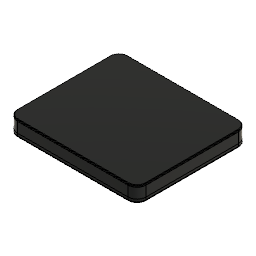
SafeWall-A-concept-v01 (Autodesk Fusion 360 design; units mm, degrees)
part number: 2026-10-03-23-20-51-672
part number: 2026-10-03-23-20-51-673
part number: 2026-10-03-23-20-51-674
part number: 2026-10-03-23-20-51-675
part number: 2026-10-03-23-20-51-676
Autodesk Fusion 360 part; units mm, degrees
sketch "01 Contact pad - silicone proposal_outline" plane through (0, 0, 0) normal (0, 0, 1) x (1, 0, 0) in component "01 Contact pad - silicone proposal"
  line L0 (9, 0) -> (119, 0)
  line L1 (128, 9) -> (128, 101)
  line L2 (119, 110) -> (9, 110)
  line L3 (0, 101) -> (0, 9)
  arc A0 (119, 0) -> (128, 9) centre (119, 9) ccw
  arc A1 (128, 101) -> (119, 110) centre (119, 101) ccw
  arc A2 (9, 110) -> (0, 101) centre (9, 101) ccw
  arc A3 (0, 9) -> (9, 0) centre (9, 9) ccw
extrude "01 Contact pad - silicone proposal" add sketch "01 Contact pad - silicone proposal_outline" along normal blind 0.6 makes body 1 in component "01 Contact pad - silicone proposal"
sketch "02 Rear panel - magnet pockets_outline" plane through (0, 0, 0) normal (0, 0, 1) x (1, 0, 0) in component "02 Rear panel - magnet pockets"
  line L0 (9, 0) -> (119, 0)
  line L1 (128, 9) -> (128, 101)
  line L2 (119, 110) -> (9, 110)
  line L3 (0, 101) -> (0, 9)
  arc A0 (119, 0) -> (128, 9) centre (119, 9) ccw
  arc A1 (128, 101) -> (119, 110) centre (119, 101) ccw
  arc A2 (9, 110) -> (0, 101) centre (9, 101) ccw
  arc A3 (0, 9) -> (9, 0) centre (9, 9) ccw
extrude "02 Rear panel - magnet pockets" add sketch "02 Rear panel - magnet pockets_outline" along normal blind 2.4 separate body makes body 2 in component "02 Rear panel - magnet pockets"
ref_plane "WorkPlane1" through (0, 0, 2.4) normal (0, 0, 1) x (1, 0, 0) in component "02 Rear panel - magnet pockets"
sketch "Magnet_ring_pocket" plane through (0, 0, 2.4) normal (0, 0, 1) x (1, 0, 0) in component "02 Rear panel - magnet pockets"
  circle A0 centre (64, 80) radius 27.55
  circle A1 centre (64, 80) radius 22.5
extrude "Ring pocket - depth provisional" cut sketch "Magnet_ring_pocket" against normal blind 2 bodies 2 in component "02 Rear panel - magnet pockets"
ref_plane "WorkPlane2" through (0, 0, 2.4) normal (0, 0, 1) x (1, 0, 0) in component "02 Rear panel - magnet pockets"
sketch "Orientation_pocket" plane through (0, 0, 2.4) normal (0, 0, 1) x (1, 0, 0) in component "02 Rear panel - magnet pockets"
  line L0 (61, 29.01) -> (67, 29.01)
  line L1 (67.5, 29.51) -> (67.5, 48.82)
  line L2 (67, 49.32) -> (61, 49.32)
  line L3 (60.5, 48.82) -> (60.5, 29.51)
  arc A0 (67, 29.01) -> (67.5, 29.51) centre (67, 29.51) ccw
  arc A1 (67.5, 48.82) -> (67, 49.32) centre (67, 48.82) ccw
  arc A2 (61, 49.32) -> (60.5, 48.82) centre (61, 48.82) ccw
  arc A3 (60.5, 29.51) -> (61, 29.01) centre (61, 29.51) ccw
extrude "Orientation pocket - depth provisional" cut sketch "Orientation_pocket" against normal blind 2 bodies 2 in component "02 Rear panel - magnet pockets"
sketch "03 Magnet ring SPACE ONLY - not magnet specification_outline" plane through (0, 0, 0) normal (0, 0, 1) x (1, 0, 0) in component "03 Magnet ring SPACE ONLY - not magnet specification"
  circle A0 centre (0, 0) radius 27.05
  circle A1 centre (0, 0) radius 23
extrude "03 Magnet ring SPACE ONLY - not magnet specification" add sketch "03 Magnet ring SPACE ONLY - not magnet specification_outline" along normal blind 1.2 separate body makes body 3 in component "03 Magnet ring SPACE ONLY - not magnet specification"
sketch "04 Orientation magnet SPACE ONLY_outline" plane through (0, 0, 0) normal (0, 0, 1) x (1, 0, 0) in component "04 Orientation magnet SPACE ONLY"
  line L0 (0, 0) -> (6, 0)
  line L1 (6, 0) -> (6, 19.31)
  line L2 (6, 19.31) -> (0, 19.31)
  line L3 (0, 19.31) -> (0, 0)
extrude "04 Orientation magnet SPACE ONLY" add sketch "04 Orientation magnet SPACE ONLY_outline" along normal blind 1.2 separate body makes body 4 in component "04 Orientation magnet SPACE ONLY"
sketch "Wall_ring" plane through (0, 0, 0) normal (0, 0, 1) x (1, 0, 0) in component "05 Perimeter walls - ports and fasteners unresolved"
  line L0 (9, 0) -> (119, 0)
  line L1 (128, 9) -> (128, 101)
  line L2 (119, 110) -> (9, 110)
  line L3 (0, 101) -> (0, 9)
  arc A0 (119, 0) -> (128, 9) centre (119, 9) ccw
  arc A1 (128, 101) -> (119, 110) centre (119, 101) ccw
  arc A2 (9, 110) -> (0, 101) centre (9, 101) ccw
  arc A3 (0, 9) -> (9, 0) centre (9, 9) ccw
  line L4 (9, 1.6) -> (119, 1.6)
  line L5 (126.4, 9) -> (126.4, 101)
  line L6 (119, 108.4) -> (9, 108.4)
  line L7 (1.6, 101) -> (1.6, 9)
  arc A4 (119, 1.6) -> (126.4, 9) centre (119, 9) ccw
  arc A5 (126.4, 101) -> (119, 108.4) centre (119, 101) ccw
  arc A6 (9, 108.4) -> (1.6, 101) centre (9, 101) ccw
  arc A7 (1.6, 9) -> (9, 1.6) centre (9, 9) ccw
extrude "Shell perimeter" add sketch "Wall_ring" along normal blind 10.2 separate body makes body 5 in component "05 Perimeter walls - ports and fasteners unresolved"
sketch "06 Battery reference - EEMB 3400mAh - not selected_outline" plane through (0, 0, 0) normal (0, 0, 1) x (1, 0, 0) in component "06 Battery reference - EEMB 3400mAh - not selected"
  line L0 (1.2, 0) -> (54.3, 0)
  line L1 (55.5, 1.2) -> (55.5, 90.8)
  line L2 (54.3, 92) -> (1.2, 92)
  line L3 (0, 90.8) -> (0, 1.2)
  arc A0 (54.3, 0) -> (55.5, 1.2) centre (54.3, 1.2) ccw
  arc A1 (55.5, 90.8) -> (54.3, 92) centre (54.3, 90.8) ccw
  arc A2 (1.2, 92) -> (0, 90.8) centre (1.2, 90.8) ccw
  arc A3 (0, 1.2) -> (1.2, 0) centre (1.2, 1.2) ccw
extrude "06 Battery reference - EEMB 3400mAh - not selected" add sketch "06 Battery reference - EEMB 3400mAh - not selected_outline" along normal blind 6.3 separate body makes body 6 in component "06 Battery reference - EEMB 3400mAh - not selected"
sketch "07 Custom carrier PCB ENVELOPE - no routing_outline" plane through (0, 0, 0) normal (0, 0, 1) x (1, 0, 0) in component "07 Custom carrier PCB ENVELOPE - no routing"
  line L0 (2, 0) -> (58, 0)
  line L1 (60, 2) -> (60, 86)
  line L2 (58, 88) -> (2, 88)
  line L3 (0, 86) -> (0, 2)
  arc A0 (58, 0) -> (60, 2) centre (58, 2) ccw
  arc A1 (60, 86) -> (58, 88) centre (58, 86) ccw
  arc A2 (2, 88) -> (0, 86) centre (2, 86) ccw
  arc A3 (0, 2) -> (2, 0) centre (2, 2) ccw
extrude "07 Custom carrier PCB ENVELOPE - no routing" add sketch "07 Custom carrier PCB ENVELOPE - no routing_outline" along normal blind 1.6 separate body makes body 7 in component "07 Custom carrier PCB ENVELOPE - no routing"
sketch "08 CM4 installed ENVELOPE incl connectors_outline" plane through (0, 0, 0) normal (0, 0, 1) x (1, 0, 0) in component "08 CM4 installed ENVELOPE incl connectors"
  line L0 (1, 0) -> (54, 0)
  line L1 (55, 1) -> (55, 39)
  line L2 (54, 40) -> (1, 40)
  line L3 (0, 39) -> (0, 1)
  arc A0 (54, 0) -> (55, 1) centre (54, 1) ccw
  arc A1 (55, 39) -> (54, 40) centre (54, 39) ccw
  arc A2 (1, 40) -> (0, 39) centre (1, 39) ccw
  arc A3 (0, 1) -> (1, 0) centre (1, 1) ccw
extrude "08 CM4 installed ENVELOPE incl connectors" add sketch "08 CM4 installed ENVELOPE incl connectors_outline" along normal blind 6.578 separate body makes body 8 in component "08 CM4 installed ENVELOPE incl connectors"
sketch "09 LTE module size reference 32x29 - model undecided_outline" plane through (0, 0, 0) normal (0, 0, 1) x (1, 0, 0) in component "09 LTE module size reference 32x29 - model undecided"
  line L0 (1, 0) -> (31, 0)
  line L1 (32, 1) -> (32, 28)
  line L2 (31, 29) -> (1, 29)
  line L3 (0, 28) -> (0, 1)
  arc A0 (31, 0) -> (32, 1) centre (31, 1) ccw
  arc A1 (32, 28) -> (31, 29) centre (31, 28) ccw
  arc A2 (1, 29) -> (0, 28) centre (1, 28) ccw
  arc A3 (0, 1) -> (1, 0) centre (1, 1) ccw
extrude "09 LTE module size reference 32x29 - model undecided" add sketch "09 LTE module size reference 32x29 - model undecided_outline" along normal blind 2.4 separate body makes body 9 in component "09 LTE module size reference 32x29 - model undecided"
sketch "10 Power and IO SPACE RESERVATION_outline" plane through (0, 0, 0) normal (0, 0, 1) x (1, 0, 0) in component "10 Power and IO SPACE RESERVATION"
  line L0 (1, 0) -> (14, 0)
  line L1 (15, 1) -> (15, 28)
  line L2 (14, 29) -> (1, 29)
  line L3 (0, 28) -> (0, 1)
  arc A0 (14, 0) -> (15, 1) centre (14, 1) ccw
  arc A1 (15, 28) -> (14, 29) centre (14, 28) ccw
  arc A2 (1, 29) -> (0, 28) centre (1, 28) ccw
  arc A3 (0, 1) -> (1, 0) centre (1, 1) ccw
extrude "10 Power and IO SPACE RESERVATION" add sketch "10 Power and IO SPACE RESERVATION_outline" along normal blind 4 separate body makes body 10 in component "10 Power and IO SPACE RESERVATION"
sketch "11 Thermal spreader CONCEPT - path unverified_outline" plane through (0, 0, 0) normal (0, 0, 1) x (1, 0, 0) in component "11 Thermal spreader CONCEPT - path unverified"
  line L0 (2, 0) -> (52, 0)
  line L1 (54, 2) -> (54, 76)
  line L2 (52, 78) -> (2, 78)
  line L3 (0, 76) -> (0, 2)
  arc A0 (52, 0) -> (54, 2) centre (52, 2) ccw
  arc A1 (54, 76) -> (52, 78) centre (52, 76) ccw
  arc A2 (2, 78) -> (0, 76) centre (2, 76) ccw
  arc A3 (0, 2) -> (2, 0) centre (2, 2) ccw
extrude "11 Thermal spreader CONCEPT - path unverified" add sketch "11 Thermal spreader CONCEPT - path unverified_outline" along normal blind 0.6 separate body makes body 11 in component "11 Thermal spreader CONCEPT - path unverified"
sketch "12 Lid - graphite proposal_outline" plane through (0, 0, 0) normal (0, 0, 1) x (1, 0, 0) in component "12 Lid - graphite proposal"
  line L0 (9, 0) -> (119, 0)
  line L1 (128, 9) -> (128, 101)
  line L2 (119, 110) -> (9, 110)
  line L3 (0, 101) -> (0, 9)
  arc A0 (119, 0) -> (128, 9) centre (119, 9) ccw
  arc A1 (128, 101) -> (119, 110) centre (119, 101) ccw
  arc A2 (9, 110) -> (0, 101) centre (9, 101) ccw
  arc A3 (0, 9) -> (9, 0) centre (9, 9) ccw
extrude "12 Lid - graphite proposal" add sketch "12 Lid - graphite proposal_outline" along normal blind 1.6 separate body makes body 12 in component "12 Lid - graphite proposal"
fillet "Lid top edge - 0.5 mm comfort radius" radius 0.5 64 edges at (0, 55, 1.6) (2.636, 2.636, 1.6) (64, 0, 1.6) (125.364, 2.636, 1.6) (128, 55, 1.6) (125.364, 107.364, 1.6) (64, 110, 1.6) (2.636, 107.364, 1.6) (2.636, 107.364, 1.6) (0, 55, 1.6) (2.636, 2.636, 1.6) (64, 0, 1.6) (125.364, 2.636, 1.6) (128, 55, 1.6) (125.364, 107.364, 1.6) (64, 110, 1.6) (64, 110, 1.6) (2.636, 107.364, 1.6) (0, 55, 1.6) (2.636, 2.636, 1.6) (64, 0, 1.6) (125.364, 2.636, 1.6) (128, 55, 1.6) (125.364, 107.364, 1.6) (125.364, 107.364, 1.6) (64, 110, 1.6) (2.636, 107.364, 1.6) (0, 55, 1.6) (2.636, 2.636, 1.6) (64, 0, 1.6) (125.364, 2.636, 1.6) (128, 55, 1.6) (128, 55, 1.6) (125.364, 107.364, 1.6) (64, 110, 1.6) (2.636, 107.364, 1.6) (0, 55, 1.6) (2.636, 2.636, 1.6) (64, 0, 1.6) (125.364, 2.636, 1.6) (125.364, 2.636, 1.6) (128, 55, 1.6) (125.364, 107.364, 1.6) (64, 110, 1.6) (2.636, 107.364, 1.6) (0, 55, 1.6) (2.636, 2.636, 1.6) (64, 0, 1.6) (64, 0, 1.6) (125.364, 2.636, 1.6) (128, 55, 1.6) (125.364, 107.364, 1.6) (64, 110, 1.6) (2.636, 107.364, 1.6) (0, 55, 1.6) (2.636, 2.636, 1.6) (2.636, 2.636, 1.6) (64, 0, 1.6) (125.364, 2.636, 1.6) (128, 55, 1.6) (125.364, 107.364, 1.6) (64, 110, 1.6) (2.636, 107.364, 1.6) (0, 55, 1.6) on bodies 12 in component "12 Lid - graphite proposal"
component "01 Contact pad - silicone proposal" placed x (1, 0, 0) y (0, 1, 0) z (0, 0, 1) at (0, 0, 0)
component "02 Rear panel - magnet pockets" placed x (1, 0, 0) y (0, 1, 0) z (0, 0, 1) at (0, 0, 0.6)
component "03 Magnet ring SPACE ONLY - not magnet specification" placed x (1, 0, 0) y (0, 1, 0) z (0, 0, 1) at (64, 80, 1.1)
component "04 Orientation magnet SPACE ONLY" placed x (1, 0, 0) y (0, 1, 0) z (0, 0, 1) at (61, 29.51, 1.1)
component "05 Perimeter walls - ports and fasteners unresolved" placed x (1, 0, 0) y (0, 1, 0) z (0, 0, 1) at (0, 0, 3)
component "06 Battery reference - EEMB 3400mAh - not selected" placed x (1, 0, 0) y (0, 1, 0) z (0, 0, 1) at (67, 7, 4)
component "07 Custom carrier PCB ENVELOPE - no routing" placed x (1, 0, 0) y (0, 1, 0) z (0, 0, 1) at (4, 10, 4)
component "08 CM4 installed ENVELOPE incl connectors" placed x (1, 0, 0) y (0, 1, 0) z (0, 0, 1) at (6.5, 52, 5.6)
component "09 LTE module size reference 32x29 - model undecided" placed x (1, 0, 0) y (0, 1, 0) z (0, 0, 1) at (9, 15, 5.6)
component "10 Power and IO SPACE RESERVATION" placed x (1, 0, 0) y (0, 1, 0) z (0, 0, 1) at (46, 15, 5.6)
component "11 Thermal spreader CONCEPT - path unverified" placed x (1, 0, 0) y (0, 1, 0) z (0, 0, 1) at (7, 14, 12.4)
component "12 Lid - graphite proposal" placed x (1, 0, 0) y (0, 1, 0) z (0, 0, 1) at (0, 0, 13.4)
equation "d7 = pad"
equation "d9 = rear"
equation "d25 = batteryT"
equation "d27 = pcb"
equation "d29 = cm4Mounted"
equation "d37 = wall"
equation "wall = 1.6 mm" comment "Packaging study value; XY outlines are regenerated from layout-study.json"
equation "rear = 2.4 mm" comment "Packaging study value; XY outlines are regenerated from layout-study.json"
equation "pad = 0.6 mm" comment "Packaging study value; XY outlines are regenerated from layout-study.json"
equation "pcb = 1.6 mm" comment "Packaging study value; XY outlines are regenerated from layout-study.json"
equation "cm4Mounted = 6.578 mm" comment "Packaging study value; XY outlines are regenerated from layout-study.json"
equation "batteryT = 6.3 mm" comment "Packaging study value; XY outlines are regenerated from layout-study.json"
named bodies: "01 Contact pad - silicone proposal", "02 Rear panel - magnet pockets", "03 Magnet ring SPACE ONLY - not magnet specification", "04 Orientation magnet SPACE ONLY", "Shell perimeter", "06 Battery reference - EEMB 3400mAh - not selected", "07 Custom carrier PCB ENVELOPE - no routing", "08 CM4 installed ENVELOPE incl connectors", "09 LTE module size reference 32x29 - model undecided", "10 Power and IO SPACE RESERVATION", "11 Thermal spreader CONCEPT - path unverified", "12 Lid - graphite proposal"
